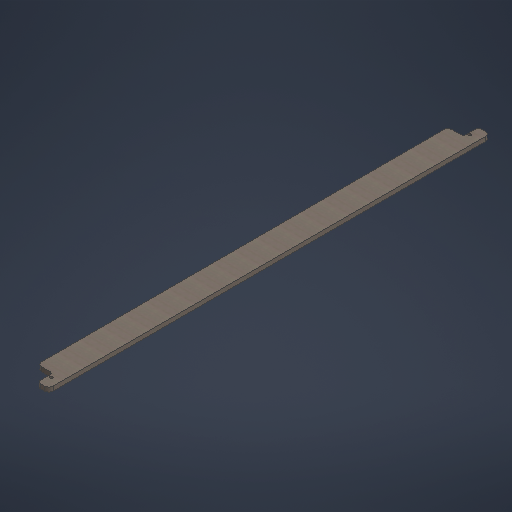
# Autodesk Inventor part: Drag Chain Support
Saved by Autodesk Inventor 2027.1 (Build 311270010, 270A)
## iProperties
Created: 2026-10-27
Part Number: Drag Chain Support
Material: Wood (Walnut)
Document SubType Name: Modeling
Designer: Ahmed
Density: 0.55 g/cm^3
Appearance: Walnut
Author: Ahmed
Autodesk Inventor part; units mm, degrees
ref_plane "YZ Plane" through (0, 0, 0) normal (1, 0, 0) x (0, 1, 0)
ref_plane "XZ Plane" through (0, 0, 0) normal (0, 1, 0) x (-1, 0, 0)
ref_plane "XY Plane" through (0, 0, 0) normal (0, 0, 1) x (1, 0, 0)
sketch "Sketch1" plane through (0, 0, 0) normal (0, 1, 0) x (-1, 0, 0)
  line L0 (10.42, 253.75) -> (-10.42, 253.75)
  line L1 (-15.42, 248.75) -> (-15.42, -248.75)
  line L2 (-10.42, -253.75) -> (10.42, -253.75)
  line L3 (15.42, -248.75) -> (15.42, 248.75)
  line L4 (15.42, 253.75) -> (-15.42, -253.75) construction
  line L5 (-15.42, 253.75) -> (15.42, -253.75) construction
  arc A0 (15.42, 248.75) -> (10.42, 253.75) centre (10.42, 248.75) ccw
  arc A1 (-10.42, 253.75) -> (-15.42, 248.75) centre (-10.42, 248.75) ccw
  arc A2 (10.42, -253.75) -> (15.42, -248.75) centre (10.42, -248.75) ccw
  arc A3 (-15.42, -248.75) -> (-10.42, -253.75) centre (-10.42, -248.75) ccw
  circle A4 centre (-5.67, 241.25) radius 1.65
  circle A5 centre (-4.67, -241.25) radius 1.65
  line L6 (-2.33, -253.75) -> (15.42, -253.75)
  line L7 (15.42, -253.75) -> (15.42, -236.25)
  line L8 (15.42, -236.25) -> (-2.33, -236.25)
  line L9 (-2.33, -236.25) -> (-2.33, -253.75)
  line L10 (15.42, 0) -> (-15.42, 0)
  line L11 (-2.33, 253.75) -> (15.42, 253.75)
  line L12 (15.42, 253.75) -> (15.42, 236.25)
  line L13 (15.42, 236.25) -> (-2.33, 236.25)
  line L14 (-2.33, 236.25) -> (-2.33, 253.75)
  point P0 (0, 0)
  point P1 (15.42, 236.25)
  dimension "d0" = 30.84
  dimension "d1" = 507.5
  dimension "d2" = 5
  dimension "d3" = 3.3
  dimension "d4" = 12.5
  dimension "d5" = 3.3
  dimension "d6" = 12.5
  dimension "d9" = 10.75
  dimension "d10" = 9.75
  dimension "d11" = 17.75
  dimension "d12" = 17.5
  constraints: 30 end point, 9 point on line, 8 point on circle, 8 tangent, 6 centre point, 4 midpoint, 4 parallel, 4 symmetric about line, 3 equal radius, 2 horizontal, 2 perpendicular, 1 collinear
  measures "d0" distance of L5.end L4.end
  measures "d1" distance of L4.end L5.start
  measures "d2" radius of A0
  measures "d3" diameter of A4
  measures "d4" distance from line of A4.centre L0
  measures "d5" diameter of A5
  measures "d6" distance from line of L2 A5.centre
  measures "d9" distance from line of A5.centre L1
  measures "d10" distance from line of L1 A4.centre
  measures "d11" distance of L8.end L7.end
  measures "d12" distance of L7.end L6.end
extrude "Extrusion1" add sketch "Sketch1" along normal blind 5 contours L14 L13 L3 L10 L1 A1 L0 | L3 L8 L9 L2 A3 L1 L10
fillet "Fillet1" radius 5 2 edges at (-15.42, 2.5, -236.25) (-15.42, 2.5, 236.25)
fillet "Fillet2" radius 3 4 edges at (2.33, 2.5, -236.25) (2.33, 2.5, 236.25) (2.33, 2.5, -253.75) (2.33, 2.5, 253.75)
equation "\"d5\" = d3"
equation "\"d6\" = d4"
body "Solid1"
